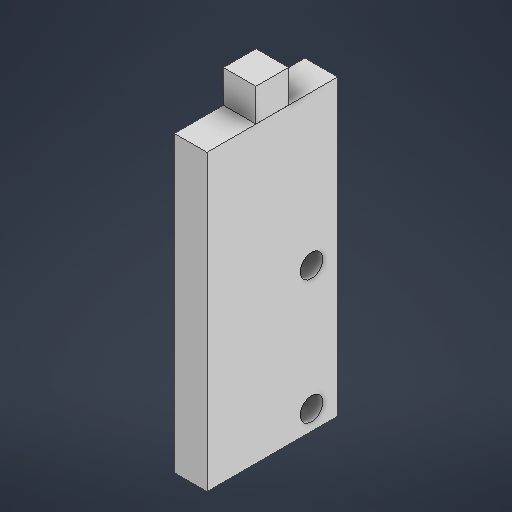
# Autodesk Inventor part: Panel
Saved by Autodesk Inventor 2025.2 (Build 292293000, 293)
## iProperties
Created: 2025-06-04
Part Number: Panel
Material: Genérico
Document SubType Name: Modeling
Designer: Niko
Density: 1 g/cm^3
Appearance: Valor por defecto
Author: Niko
Autodesk Inventor part; units mm, degrees
ref_plane "YZ Plane" through (0, 0, 0) normal (1, 0, 0) x (0, 1, 0)
ref_plane "XZ Plane" through (0, 0, 0) normal (0, 1, 0) x (-1, 0, 0)
ref_plane "XY Plane" through (0, 0, 0) normal (0, 0, 1) x (1, 0, 0)
sketch "Boceto1" plane through (0, 0, 0) normal (1, 0, 0) x (0, 1, 0)
  line L0 (22.5, 10) -> (-22.5, 10)
  line L1 (-22.5, 10) -> (-22.5, -10)
  line L2 (-22.5, -10) -> (22.5, -10)
  line L3 (22.5, 10) -> (22.5, 2.5)
  line L4 (22.5, 2.5) -> (27.5, 2.5)
  line L5 (27.5, 2.5) -> (27.5, -2.5)
  line L6 (27.5, -2.5) -> (22.5, -2.5)
  line L7 (22.5, -2.5) -> (22.5, -10)
  line L8 (-22.5, 0) -> (-22.5, -5)
  line L9 (-22.5, -10) -> (-22.5, -6)
  circle A0 centre (-19.5, -6) radius 1.75
  circle A1 centre (-0.5, -6) radius 1.75
  constraints: 20 end point, 5 perpendicular, 3 point on line, 2 centre point, 1 horizontal, 1 midpoint, 1 parallel, 1 vertical
extrude "Extrusión3" add sketch "Boceto1" along normal blind 5
sketch "Boceto2" plane through (5, 0, 0) normal (1, 0, 0) x (0, 0, -1)
  line L0 (10, 22.5) -> (2.5, 22.5) projected
  line L1 (-2.5, 27.5) -> (-2.5, 22.5) projected
  line L2 (2.5, 22.5) -> (-2.5, 22.5)
  line L3 (-2.5, 22.5) -> (-2.5, 27.5)
  line L4 (-2.5, 27.5) -> (2.5, 27.5)
  line L5 (2.5, 27.5) -> (2.5, 22.5)
  point P0 (0, 0)
  constraints: 8 end point, 2 parallel, 1 horizontal, 1 perpendicular
extrude "Extrusión4" cut sketch "Boceto2" against normal blind 0.01
sketch "Boceto3" plane through (0, 0, 0) normal (-1, 0, 0) x (0, 0, 1)
  line L0 (-2.5, 22.5) -> (-2.5, 27.5) projected
  line L1 (2.5, 22.5) -> (10, 22.5) projected
  line L2 (-2.5, 27.5) -> (2.5, 27.5)
  line L3 (2.5, 27.5) -> (2.5, 22.5)
  line L4 (2.5, 22.5) -> (-2.5, 22.5)
  line L5 (-2.5, 22.5) -> (-2.5, 27.5)
  point P0 (0, 0)
  constraints: 8 end point, 2 parallel, 1 horizontal, 1 perpendicular
extrude "Extrusión5" cut sketch "Boceto3" against normal blind 0.01
